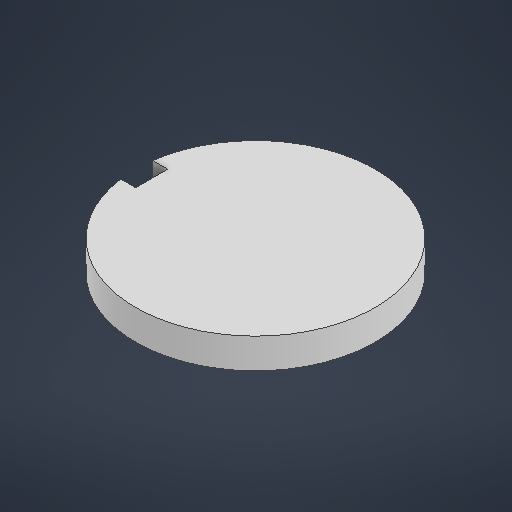
# Autodesk Inventor part: Parachute bulkhead_1
Saved by Autodesk Inventor 2027 (Build 310192060, 192F)
## iProperties
Created: 2026-10-03
Part Number: Parachute bulkhead_1
Material: Generic
Document SubType Name: Modeling
Designer: troop
Density: 1 g/cm^3
Appearance: Default
Author: troop
Autodesk Inventor part; units mm, degrees
ref_plane "YZ Plane" through (0, 0, 0) normal (1, 0, 0) x (0, 1, 0)
ref_plane "XZ Plane" through (0, 0, 0) normal (0, 1, 0) x (-1, 0, 0)
ref_plane "XY Plane" through (0, 0, 0) normal (0, 0, 1) x (1, 0, 0)
sketch "Sketch1" plane through (0, 0, 0) normal (0, 1, 0) x (-1, 0, 0)
  circle A0 centre (0, 0) radius 37.973
  line L0 (32.893, 5.08) -> (37.973, 5.08)
  line L1 (37.973, 5.08) -> (37.973, -5.08)
  line L2 (37.973, -5.08) -> (32.893, -5.08)
  line L3 (32.893, -5.08) -> (32.893, 5.08)
  point P0 (37.973, 0)
  point P1 (37.6317, 5.08)
  point P2 (37.6317, -5.08)
  dimension "d0" = 75.946
  dimension "d2" = 5.08
  dimension "d6" = 10.16
  dimension "d7" = 0
  constraints: 8 end point, 2 parallel, 1 coincident, 1 horizontal, 1 midpoint, 1 perpendicular, 3 other
  measures "d2" distance of L1.end L2.end
  measures "d6" distance of L2.end L0.start
  measures "d7" vertical distance of point (0, 0) point (37.973, 0)
extrude "Extrusion1" add sketch "Sketch1" along normal blind 9.525 contours L0 L3 L2 A0 picked at (9.3494, 1.407)
body "Solid1"
